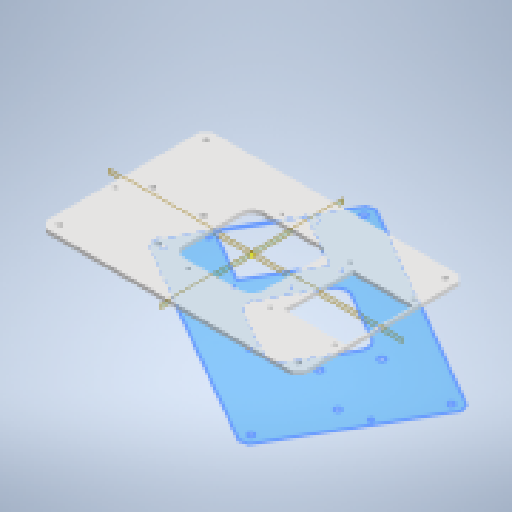
# Autodesk Inventor part: commutation_board
Saved by Autodesk Inventor 2025 (Build 290162000, 162)
## iProperties
Created: 2026-10-19
Part Number: commutation_board
Material: Типовые
Document SubType Name: Modeling
Designer: garin
Density: 1 g/cm^3
Appearance: По умолчанию
Author: garin
Autodesk Inventor part; units mm, degrees
ref_plane "YZ Plane" through (0, 0, 0) normal (1, 0, 0) x (0, 1, 0)
ref_plane "XZ Plane" through (0, 0, 0) normal (0, 1, 0) x (-1, 0, 0)
ref_plane "XY Plane" through (0, 0, 0) normal (0, 0, 1) x (1, 0, 0)
sketch "Эскиз1" plane through (0, 0, 0) normal (0, 1, 0) x (-1, 0, 0)
  point P0 (0, 0)
sketch "Эскиз2" plane through (0, 0, 0) normal (0, 1, 0) x (-1, 0, 0)
  line L0 (-64.5, -41.5) -> (64.5, -41.5)
  line L1 (64.5, -41.5) -> (64.5, 41.5)
  line L2 (64.5, 41.5) -> (-64.5, 41.5)
  line L3 (-64.5, 41.5) -> (-64.5, -41.5)
  line L4 (-64.5, -41.5) -> (64.5, 41.5) construction
  line L5 (64.5, -41.5) -> (-64.5, 41.5) construction
  line L6 (-64.5, 41.5) -> (-59.5, 41.5) construction
  line L7 (-59.5, 41.5) -> (-59.5, 36.5) construction
  line L8 (-59.5, 36.5) -> (-64.5, 36.5) construction
  line L9 (-64.5, 36.5) -> (-64.5, 41.5) construction
  circle A0 centre (-59.5, 36.5) radius 1.35
  line L10 (0, 41.5) -> (0, -41.5) construction
  line L11 (64.5, 0) -> (-64.5, 0) construction
  circle A1 centre (59.5, 36.5) radius 1.35
  circle A2 centre (-59.5, -36.5) radius 1.35
  circle A3 centre (59.5, -36.5) radius 1.35
  line L12 (-64.5, 41.5) -> (-67.5, 41.5)
  line L13 (-67.5, 41.5) -> (-67.5, -41.5)
  line L14 (-67.5, -41.5) -> (-64.5, -41.5)
  line L15 (-64.5, -41.5) -> (-64.5, 41.5)
  circle A4 centre (-60.9154, 19.7453) radius 1 projected
  circle A5 centre (-28.8714, 19.7547) radius 1 projected
  circle A6 centre (-28.9038, -19.7453) radius 1 projected
  circle A7 centre (-60.9038, -19.7547) radius 1 projected
  circle A8 centre (-23.4, 0) radius 1 projected
  circle A9 centre (8.5169, 23.4) radius 1 projected
  circle A10 centre (8.5169, -23.4) radius 1 projected
  line L16 (-62.0062, -14.4325) -> (-33.1512, -14.4241) projected
  line L17 (-33.1512, -14.4241) -> (-33.1597, 14.4309) projected
  line L18 (-33.1597, 14.4309) -> (-62.0146, 14.4225) projected
  line L19 (-62.0146, 14.4225) -> (-62.0062, -14.4325) projected
  line L20 (-61.0065, -13.4322) -> (-61.0144, 13.4228) projected
  line L21 (-61.0144, 13.4228) -> (-34.1594, 13.4307) projected
  line L22 (-34.1594, 13.4307) -> (-34.1515, -13.4243) projected
  line L23 (-34.1515, -13.4243) -> (-61.0065, -13.4322) projected
  arc A11 (-13.75, 19.2941) -> (-19.2941, 13.75) centre (-13.75, 13.75) ccw projected
  line L24 (-19.2941, -13.75) -> (-19.2941, 13.75) projected
  arc A12 (-19.2941, -13.75) -> (-13.75, -19.2941) centre (-13.75, -13.75) ccw projected
  line L25 (-13.75, -19.2941) -> (3.6284, -19.2941) projected
  arc A13 (13.75, -19.2941) -> (19.2941, -13.75) centre (13.75, -13.75) ccw projected
  line L26 (13.75, -19.2941) -> (-13.75, -19.2941) projected
  line L27 (19.2941, 13.75) -> (19.2941, -13.75) projected
  line L28 (-13.75, 19.2941) -> (13.75, 19.2941) projected
  arc A14 (19.2941, 13.75) -> (13.75, 19.2941) centre (13.75, 13.75) ccw projected
  circle A15 centre (26.7, 20) radius 1.5 projected
  circle A16 centre (52.5, -3) radius 1.5 projected
  circle A17 centre (27.5, -3) radius 1.5 projected
  arc A18 (-13.75, 19.6941) -> (-19.6941, 13.75) centre (-13.75, 13.75) ccw
  line L29 (-13.75, 19.6941) -> (13.75, 19.6941)
  arc A19 (19.6941, 13.75) -> (13.75, 19.6941) centre (13.75, 13.75) ccw
  line L30 (19.6941, 13.75) -> (19.6941, -13.75)
  arc A20 (13.75, -19.6941) -> (19.6941, -13.75) centre (13.75, -13.75) ccw
  line L31 (13.75, -19.6941) -> (-13.75, -19.6941)
  arc A21 (-19.6941, -13.75) -> (-13.75, -19.6941) centre (-13.75, -13.75) ccw
  line L32 (-19.6941, -13.75) -> (-19.6941, 13.75)
  line L33 (-62.9056, -16.4053) -> (-62.9152, 16.3947) projected
  line L34 (-29.9056, -16.3956) -> (-62.9056, -16.4053) projected
  line L35 (-29.9152, 16.4044) -> (-29.9056, -16.3956) projected
  line L36 (-62.9152, 16.3947) -> (-29.9152, 16.4044) projected
  line L37 (-62.0062, -14.4325) -> (-33.1512, -14.4241) projected
  line L38 (-62.0146, 14.4225) -> (-62.0062, -14.4325) projected
  line L39 (-33.1597, 14.4309) -> (-62.0146, 14.4225) projected
  line L40 (-33.1512, -14.4241) -> (-33.1597, 14.4309) projected
  line L41 (-33.0964, -16.8953) -> (-33.0964, 16.9047) projected
  line L42 (-33.0964, 16.9047) -> (-63.5964, 16.9047) projected
  line L43 (-63.5964, 16.9047) -> (-63.5964, -16.8953) projected
  line L44 (-63.5964, -16.8953) -> (-33.0964, -16.8953) projected
  line L45 (61.4922, 6.7178) -> (61.6778, 6.7178) construction
  line L46 (61.6778, 6.7178) -> (61.6778, 6.5322) construction
  line L47 (61.6778, 6.5322) -> (61.4922, 6.5322) construction
  line L48 (61.4922, 6.5322) -> (61.4922, 6.7178) construction
  line L49 (61.585, 6.5322) -> (61.585, 6.7178) construction
  line L50 (61.4922, 6.625) -> (61.6778, 6.625) construction
  circle A22 centre (61.585, 6.625) radius 1
  point P0 (0, 0)
  dimension "d0" = 129
  dimension "d1" = 83
  dimension "d4" = 5
  dimension "d5" = 5
  dimension "d6" = 2.7
  dimension "d10" = 3
  dimension "d11" = 83
  dimension "d12" = 0.4
  dimension "d13" = 2
  constraints: 44 end point, 11 midpoint, 9 centre point, 8 point on circle, 6 parallel, 3 horizontal, 3 perpendicular, 3 symmetric about line, 1 coincident, 10 other
  measures "d0" distance of L2.end L1.end
  measures "d1" distance of L1.end L0.end
  measures "d4" distance of L7.end L8.end
  measures "d5" distance of L6.end L7.end
  measures "d6" diameter of A0
  measures "d10" distance of L14.end L13.end
  measures "d11" distance of L13.end L12.end
  measures "d12" radial gap between concentric circles of A11 A18
  measures "d13" diameter of A22
extrude "Выдавливание1" add sketch "Эскиз2" along normal blind 2 contours L3 L2 L1 L0 | L41 L36 L35 L34
ref_plane "РабПлоскость1" through (-64.5, 0, 0) normal (0, 0, 1) x (1, 0, 0)
ref_plane "РабПлоскость2" through (0, 0, -41.5) normal (-1, 0, 0) x (0, 0, 1)
chamfer "Фаска1" distance 3 angle 45 4 edges at (64.5, 1, 41.5) (64.5, 1, -41.5) (-64.5, 1, -41.5) (-64.5, 1, 41.5)
